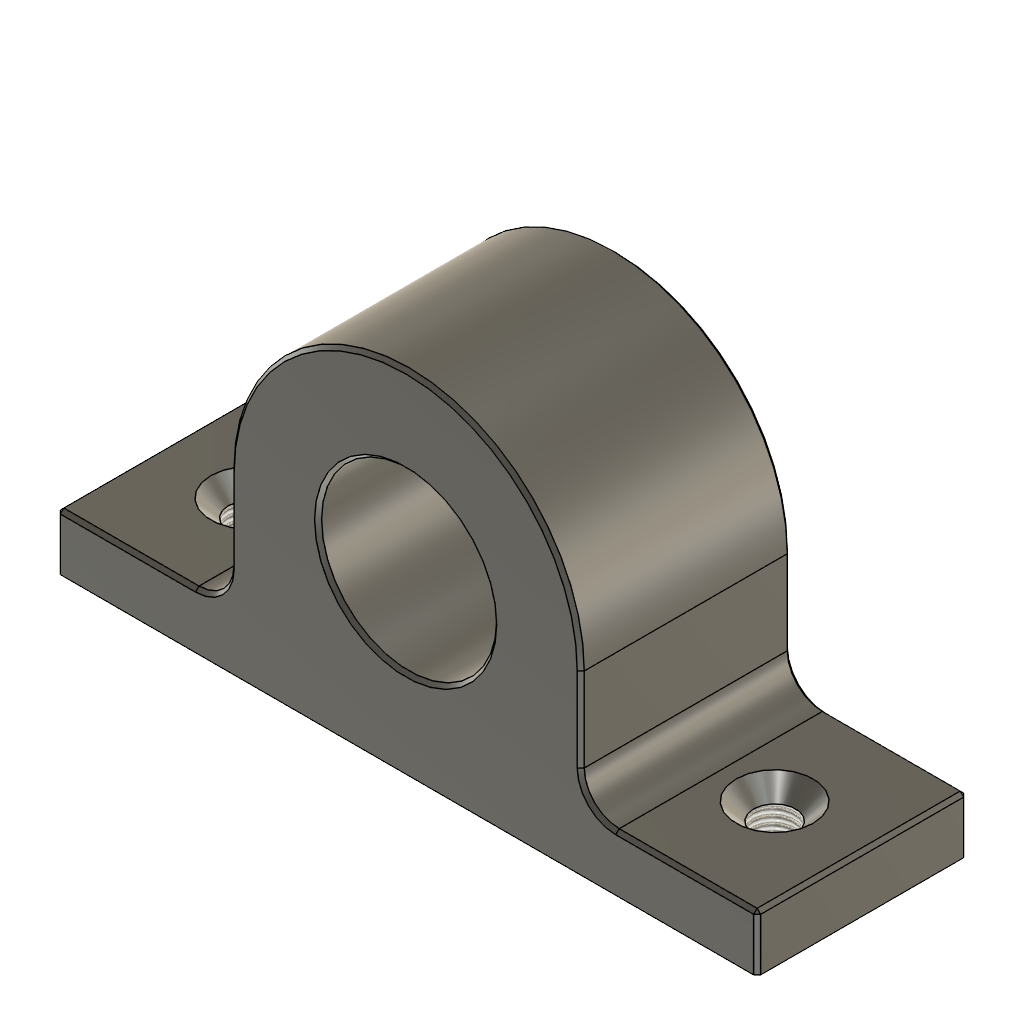
Mounting Bracket (Autodesk Fusion 360 design; units mm, degrees)
part number: 2026-11-18-19-44-24-545
Autodesk Fusion 360 part; units mm, degrees
sketch "Sketch1" plane through (0, 0, 0) normal (0, 1, 0) x (1, 0, 0)
  line L0 (0, 0) -> (100, 0)
  line L1 (100, 0) -> (100, -8)
  line L2 (100, -8) -> (0, -8)
  line L3 (0, -8) -> (0, 0)
  circle A0 centre (49.8142, -25) radius 12.5
  line L4 (24.8142, -25) -> (74.8142, -25)
  line L5 (74.8142, -25) -> (74.8142, -8)
  line L6 (74.8142, -8) -> (24.8142, -8)
  line L7 (24.8142, -8) -> (24.8142, -25)
  arc A1 (24.8142, -25) -> (74.8142, -25) centre (49.8142, -25) ccw
  dimension "d1" = 100
  dimension "d2" = 8
  dimension "d3" = 50
  dimension "d4" = 25
  dimension "d5" = 25
  dimension "d6" = 17
  dimension "d7" = 50
  constraint horizontal L0
  constraint vertical L1
  constraint horizontal L2
  constraint vertical L3
  constraint coincident L0.start L3.end
  constraint concentric A0 A1
  constraint horizontal L4
  constraint vertical L5
  constraint horizontal L6
  constraint vertical L7
  constraint coincident L2 L5.end
  measures "d1" distance of L0.start L0.end
  measures "d2" distance of L0.start L2.end
  measures "d3" diameter of A1
  measures "d4" vertical distance of L0.start A0.centre
  measures "d5" diameter of A0
  measures "d6" distance of L4.start L6.end
  measures "d7" distance of L5.end L6.end
extrude "Extrude1" add sketch "Sketch1" along normal blind 30 contours L0 L1 L2 L3 L6 | L2 A0 L4 L5 L6 L7 | A0 L4 A1
sketch "Sketch2" plane through (0, 0, 8) normal (0, 0, 1) x (-1, 0, 0)
  line L0 (-74.8142, 0) -> (-100, 0)
  line L1 (-100, 0) -> (-100, -30)
  line L2 (-100, -30) -> (-74.8142, -30)
  line L3 (-74.8142, -30) -> (-74.8142, 0)
  line L4 (0, 0) -> (0, -30)
  line L5 (0, -30) -> (-24.8142, -30)
  point P0 (-87.5, -15)
  point P1 (-12.5, -15)
  dimension "d10" = 12.5
  dimension "d11" = 15
  dimension "d12" = 12.5
  dimension "d13" = 15
  measures "d10" distance of L1 P0
  measures "d11" distance of L2 P0
  measures "d12" distance of P1 L4
  measures "d13" distance of P1 L5
hole "Hole1" at (12.5, 15, 8) at (87.5, 15, 8) direction (0, 0, -1) diameter 6.036 end through all countersink diameter 11 countersink angle 90
thread "Thread1" "ISO Metric profile 7.0 M7x1 M7x1 6H" major diameter 7.1472 minor diameter 6.0355 pitch 1 angle 60 resizes the face on face at (87.6504, 18.0142, 3.6787) on face at (12.8005, 11.997, 3.6787)
fillet "Fillet1" radius 5 2 edges at (74.8142, 15, 8) (24.8142, 15, 8)
chamfer "Chamfer1" distance 0.5 angle 45 21 edges at (9.9071, 0, 8) (89.9071, 0, 8) (76.2786, 0, 9.4645) (74.8142, 0, 19) (49.8142, 0, 50) (24.8142, 0, 19) (23.3497, 0, 9.4645) (0, 0, 4) (100, 0, 4) (38.1601, 0, 20.4798) (100, 15, 8) (89.9071, 30, 8) (9.9071, 30, 8) (23.3497, 30, 9.4645) (24.8142, 30, 19) (49.8142, 30, 50) (74.8142, 30, 19) (76.2786, 30, 9.4645) (100, 30, 4) (0, 30, 4) (0, 15, 8) tangent chain off
